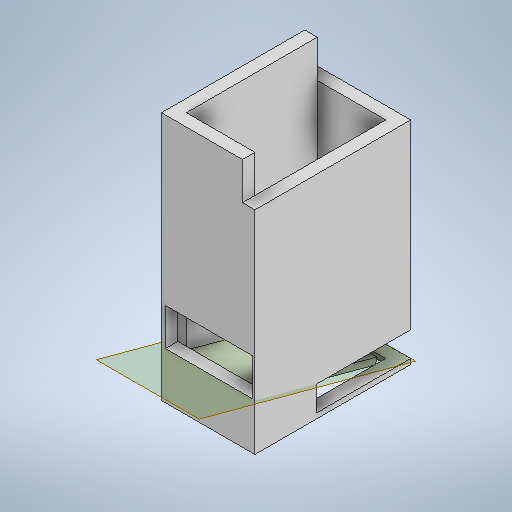
# Autodesk Inventor part: Semesterprojekt1magnetpakholder3
Saved by Autodesk Inventor 2027.1 (Build 311270010, 270A)
## iProperties
Created: 2026-10-29
Part Number: Semesterprojekt1magnetpakholder3
Material: Generic
Document SubType Name: Modeling
Designer: Sif Isaksen
Density: 1 g/cm^3
Appearance: Default
Author: Sif Isaksen
Autodesk Inventor part; units mm, degrees
ref_plane "YZ Plane" through (0, 0, 0) normal (1, 0, 0) x (0, 1, 0)
ref_plane "XZ Plane" through (0, 0, 0) normal (0, 1, 0) x (-1, 0, 0)
ref_plane "XY Plane" through (0, 0, 0) normal (0, 0, 1) x (1, 0, 0)
sketch "Sketch1" plane through (0, 0, 0) normal (0, 1, 0) x (-1, 0, 0)
  line L0 (15.4113, 32.5288) -> (4.4113, 32.5288)
  line L1 (4.4113, 32.5288) -> (4.4113, 11.5288)
  line L2 (4.4113, 11.5288) -> (15.4113, 11.5288)
  line L3 (15.4113, 11.5288) -> (15.4113, 32.5288)
  line L4 (17.4113, 34.5288) -> (2.4113, 34.5288)
  line L5 (2.4113, 34.5288) -> (2.4113, 9.5288)
  line L6 (2.4113, 9.5288) -> (17.4113, 9.5288)
  line L7 (17.4113, 9.5288) -> (17.4113, 34.5288)
  point P0 (0, 0)
  dimension "d0" = 11
  dimension "d1" = 21
  dimension "d2" = 15
  dimension "d3" = 25
  dimension "d4" = 2
  dimension "d5" = 2
  constraints: 16 end point, 4 parallel, 2 horizontal, 2 perpendicular
  measures "d0" distance of L2.end L1.end
  measures "d1" distance of L1.end L0.end
  measures "d2" distance of L6.end L5.end
  measures "d3" distance of L5.end L4.end
  measures "d4" distance between parallel lines of L7 L3
  measures "d5" distance between parallel lines of L4 L0
extrude "Extrusion1" add sketch "Sketch1" along normal blind 27
sketch "Sketch2" plane through (0, 27, 0) normal (0, 1, 0) x (1, 0, 0)
  line L0 (-15.4113, -32.5288) -> (-15.4113, -11.5288) projected
  line L1 (-17.4113, -34.5288) -> (-2.4113, -34.5288) projected
  line L2 (-15.4113, -32.5288) -> (-2.4113, -32.5288)
  line L3 (-2.4113, -32.5288) -> (-2.4113, -34.5288)
  line L4 (-2.4113, -34.5288) -> (-15.4113, -34.5288)
  line L5 (-15.4113, -34.5288) -> (-15.4113, -32.5288)
  line L6 (-17.4113, -9.5288) -> (-17.4113, -34.5288) projected
  line L7 (-15.4113, -11.5288) -> (-4.4113, -11.5288) projected
  line L8 (-17.4113, -34.5288) -> (-15.4113, -34.5288)
  line L9 (-15.4113, -34.5288) -> (-15.4113, -11.5288)
  line L10 (-15.4113, -11.5288) -> (-17.4113, -11.5288)
  line L11 (-17.4113, -11.5288) -> (-17.4113, -34.5288)
  point P0 (0, 0)
  constraints: 16 end point, 4 parallel, 2 horizontal, 2 perpendicular
extrude "Extrusion2" add sketch "Sketch2" along normal blind 6 contours L5 L1 L6 L10 L0
sketch "Sketch3" plane through (0, 27, 0) normal (0, 1, 0) x (1, 0, 0)
  line L0 (-15.4113, -34.5288) -> (-2.4113, -34.5288) projected
  line L1 (-4.4113, -32.5288) -> (-15.4113, -32.5288) projected
  line L2 (-15.4113, -34.5288) -> (-4.4113, -34.5288)
  line L3 (-4.4113, -34.5288) -> (-4.4113, -32.5288)
  line L4 (-4.4113, -32.5288) -> (-15.4113, -32.5288)
  line L5 (-15.4113, -32.5288) -> (-15.4113, -34.5288)
  point P0 (0, 0)
  point P1 (-4.4113, -34.5288)
  constraints: 8 end point, 2 parallel, 1 horizontal, 1 perpendicular
extrude "Extrusion3" add sketch "Sketch3" along normal blind 6
ref_plane "Work Plane1" through (-4.4113, 0, 32.5288) normal (0, -0.9659, 0.2588) x (-1, 0, 0)
sketch "Sketch4" plane through (-4.4113, 0, 32.5288) normal (0, -0.9659, 0.2588) x (-1, 0, 0)
  line L0 (0, 0) -> (11, 0) projected
  line L1 (0, 0) -> (11, 0)
  line L2 (11, 0) -> (11, 20.28)
  line L3 (11, 20.28) -> (0, 20.28)
  line L4 (0, 20.28) -> (0, 0)
  point P0 (-4.4113, 31.4205)
  dimension "d13" = 11
  dimension "d14" = 20.28
  constraints: 8 end point, 2 parallel, 1 horizontal, 1 perpendicular
  measures "d13" distance of L3.end L2.end
  measures "d14" distance of L2.end L1.end
extrude "Extrusion4" add sketch "Sketch4" along normal blind 1
sketch "Sketch6" plane through (-2.4113, 0, 34.5288) normal (0, 0, 1) x (1, 0, 0)
  line L0 (-13, 0.5359) -> (-0.366, 0.5359) projected
  line L1 (-0.366, 0.5359) -> (-14.366, 0.5359)
  line L2 (-14.366, 0.5359) -> (-14.366, 6.5359)
  line L3 (-14.366, 6.5359) -> (-0.366, 6.5359)
  line L4 (-0.366, 6.5359) -> (-0.366, 0.5359)
  point P0 (2.4113, 0)
  dimension "d19" = 14
  dimension "d20" = 6
  constraints: 8 end point, 2 parallel, 1 horizontal, 1 perpendicular
  measures "d19" distance of L2.end L3.end
  measures "d20" distance of L1.end L2.end
extrude "Extrusion6" cut sketch "Sketch6" against normal blind 2
sketch "Sketch7" plane through (0, 0, 0) normal (0, -1, 0) x (1, 0, 0)
  line L0 (-4.4113, 32.7877) -> (-15.4113, 32.7877) projected
  line L1 (-15.4113, 11.5288) -> (-4.4113, 11.5288) projected
  line L2 (-15.4113, 32.7877) -> (-4.4113, 32.7877)
  line L3 (-4.4113, 32.7877) -> (-4.4113, 11.5288)
  line L4 (-4.4113, 11.5288) -> (-15.4113, 11.5288)
  line L5 (-15.4113, 11.5288) -> (-15.4113, 32.7877)
  line L6 (-17.4113, 9.5288) -> (-17.4113, 34.5288) projected
  line L7 (-2.4113, 34.5288) -> (-2.4113, 9.5288) projected
  line L8 (-17.4113, 34.5288) -> (-2.4113, 34.5288)
  line L9 (-2.4113, 34.5288) -> (-2.4113, 9.5288)
  line L10 (-2.4113, 9.5288) -> (-17.4113, 9.5288)
  line L11 (-17.4113, 9.5288) -> (-17.4113, 34.5288)
  point P0 (0, 0)
  constraints: 16 end point, 4 parallel, 2 horizontal, 2 perpendicular
extrude "Extrusion7" add sketch "Sketch7" along normal blind 7
sketch "Sketch9" plane through (-2.4113, 27, 9.5288) normal (0, 0, -1) x (-1, 0, 0)
  line L0 (2, -33.1628) -> (13.4192, -33.1628) projected
  line L1 (0, -34) -> (0, 0) projected
  line L2 (13.4192, -33.1628) -> (0, -33.1628)
  line L3 (0, -33.1628) -> (0, -29.1628)
  line L4 (0, -29.1628) -> (13.4192, -29.1628)
  line L5 (13.4192, -29.1628) -> (13.4192, -33.1628)
  point P0 (-2.4113, -27)
  dimension "d27" = 4
  constraints: 8 end point, 2 parallel, 1 horizontal, 1 perpendicular, 1 point on line
  measures "d27" distance of L2.end L3.end
extrude "Extrusion9" cut sketch "Sketch9" against normal blind 2
sketch "Sketch10" plane through (-2.4113, 27, 9.5288) normal (0, 0, -1) x (-1, 0, 0)
  line L0 (13.4192, -29.1628) -> (13.4192, -33.1628) projected
  line L1 (15, -34) -> (15, 0) projected
  line L2 (13.4192, -33.1628) -> (15, -33.1628)
  line L3 (15, -33.1628) -> (15, -29.1628)
  line L4 (15, -29.1628) -> (13.4192, -29.1628)
  line L5 (13.4192, -29.1628) -> (13.4192, -33.1628)
  point P0 (-2.4113, -27)
  dimension "d30" = 4
  constraints: 8 end point, 2 parallel, 1 horizontal, 1 perpendicular, 1 point on line
  measures "d30" distance of L3.end L2.end
extrude "Extrusion10" cut sketch "Sketch10" against normal blind 2
sketch "Sketch11" plane through (-17.4113, 27, 11.5288) normal (-1, 0, 0) x (0, 0, 1)
  line L0 (-2, -33.1628) -> (0, -33.1628) projected
  line L1 (0, -33.1628) -> (13.1847, -33.1628)
  line L2 (13.1847, -33.1628) -> (13.1847, -29.1628)
  line L3 (13.1847, -29.1628) -> (0, -29.1628)
  line L4 (0, -29.1628) -> (0, -33.1628)
  point P0 (-11.5288, -27)
  dimension "d33" = 4
  constraints: 8 end point, 2 parallel, 1 horizontal, 1 perpendicular
  measures "d33" distance of L2.end L1.end
extrude "Extrusion11" cut sketch "Sketch11" against normal blind 2
sketch "Sketch12" plane through (-2.4113, 27, 34.5288) normal (1, 0, 0) x (0, 0, -1)
  line L0 (23, -33.1628) -> (23, -32.6269) projected
  line L1 (23, -33.1628) -> (9.8774, -33.1628)
  line L2 (9.8774, -33.1628) -> (9.8774, -29.1628)
  line L3 (9.8774, -29.1628) -> (23, -29.1628)
  line L4 (23, -29.1628) -> (23, -33.1628)
  point P0 (34.5288, -27)
  dimension "d36" = 4
  constraints: 8 end point, 2 parallel, 1 horizontal, 1 perpendicular
  measures "d36" distance of L1.end L2.end
extrude "Extrusion12" cut sketch "Sketch12" against normal blind 2
body "Solid1"
